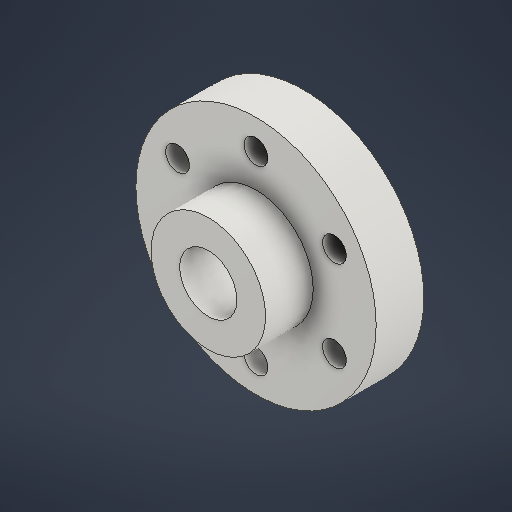
# Autodesk Inventor part: cubo_e_eixo
Saved by Autodesk Inventor 2026 (Build 300175000, 175)
## iProperties
Created: 2025-04-24
Part Number: cubo_e_eixo
Material: Genérico
Document SubType Name: Modeling
Designer: MARIA
Density: 1 g/cm^3
Appearance: Padrão
Author: MARIA
Autodesk Inventor part; units mm, degrees
ref_plane "YZ Plane" through (0, 0, 0) normal (1, 0, 0) x (0, 1, 0)
ref_plane "XZ Plane" through (0, 0, 0) normal (0, 1, 0) x (-1, 0, 0)
ref_plane "XY Plane" through (0, 0, 0) normal (0, 0, 1) x (1, 0, 0)
sketch "Esboço1" plane through (0, 0, 0) normal (0, 0, 1) x (1, 0, 0)
  circle A0 centre (0, 0) radius 12.6
  circle A1 centre (0, 0) radius 3
  dimension "d0" = 25.2
  dimension "d1" = 6
  constraints: 2 centre point, 2 coincident
  measures "d0" diameter of A0
  measures "d1" diameter of A1
extrude "Extrusão1" add sketch "Esboço1" along normal blind 5
sketch "Esboço2" plane through (0, 0, 5) normal (0, 0, 1) x (1, 0, 0)
  circle A0 centre (0, 0) radius 6
  circle A1 centre (0, 0) radius 3
  dimension "d4" = 12
  dimension "d5" = 6
  constraints: 2 centre point, 2 coincident
  measures "d4" diameter of A0
  measures "d5" diameter of A1
extrude "Extrusão2" add sketch "Esboço2" along normal blind 5
sketch "Esboço3" plane through (0, 0, 5) normal (0, 0, 1) x (1, 0, 0)
  circle A0 centre (0, 9.5) radius 1.25
  circle A1 centre (0, 0) radius 6 projected
  dimension "d8" = 2.5
  dimension "d9" = 9.5
  dimension "d10" = 0
  constraints: 1 centre point
  measures "d8" diameter of A0
  measures "d9" distance of A1.centre A0.centre
  measures "d10" horizontal distance of A1.centre A0.centre
extrude "Extrusão3" cut sketch "Esboço3" against normal through all contours A0
pattern_circular "Padrão circular1" count 6 over 360 about axis through (0, 0, 0) along (0, 0, 1) of "Extrusão3"
